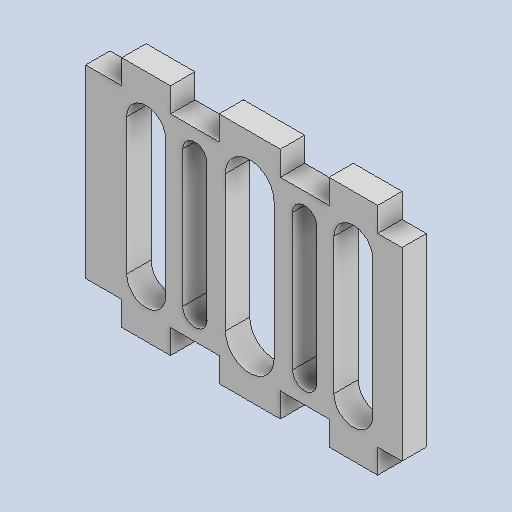
# Autodesk Inventor part: CalfFrontL
Saved by Autodesk Inventor 2025.2 (Build 292293000, 293)
## iProperties
Created: 2025-06-24
Part Number: CalfFrontL
Material: Generic
Document SubType Name: Modeling
Designer: ricoa
Density: 1 g/cm^3
Appearance: Default
Author: ricoa
Autodesk Inventor part; units mm, degrees
ref_plane "YZ Plane" through (0, 0, 0) normal (1, 0, 0) x (0, 1, 0)
ref_plane "XZ Plane" through (0, 0, 0) normal (0, 1, 0) x (-1, 0, 0)
ref_plane "XY Plane" through (0, 0, 0) normal (0, 0, 1) x (1, 0, 0)
sketch "Sketch1" plane through (0, 0, 0) normal (0, 0, 1) x (1, 0, 0)
  line L0 (17.4303, 49.3434) -> (30, 49.3434) projected
  line L1 (-2.5697, 49.3434) -> (7.4303, 49.3434) projected
  line L2 (40, 49.3434) -> (50, 49.3434) projected
  line L3 (50, 49.3434) -> (50, 44.3434)
  line L4 (40, 49.3434) -> (40, 44.3434)
  line L5 (40, 44.3434) -> (30, 44.3434)
  line L6 (30, 44.3434) -> (30, 49.3434)
  line L7 (30, 49.3434) -> (17.4303, 49.3434)
  line L8 (17.4303, 49.3434) -> (17.4303, 44.3434)
  line L9 (17.4303, 44.3434) -> (7.4303, 44.3434)
  line L10 (7.4303, 44.3434) -> (7.4303, 49.3434)
  line L11 (-2.5697, 49.3434) -> (-2.5697, 44.3434)
  line L12 (-10, 44.3434) -> (-2.5697, 44.3434) projected
  line L13 (50, 44.3434) -> (55, 44.3434) projected
  line L14 (50, 44.3434) -> (50, 49.3434) projected
  line L15 (55, 44.3434) -> (55, 6.3434)
  line L16 (55, 25.3434) -> (-10, 25.3434) construction
  line L17 (-10, 44.3434) -> (-10, 6.3434)
  line L18 (-10, 6.3434) -> (-2.5697, 6.3434)
  line L19 (-2.5697, 6.3434) -> (-2.5697, 1.3434)
  line L20 (-2.5697, 1.3434) -> (7.4303, 1.3434)
  line L21 (7.4303, 1.3434) -> (7.4303, 6.3434)
  line L22 (7.4303, 6.3434) -> (17.4303, 6.3434)
  line L23 (17.4303, 6.3434) -> (17.4303, 1.3434)
  line L24 (17.4303, 1.3434) -> (30, 1.3434)
  line L25 (30, 1.3434) -> (30, 6.3434)
  line L26 (30, 6.3434) -> (40, 6.3434)
  line L27 (40, 6.3434) -> (40, 1.3434)
  line L28 (40, 1.3434) -> (50, 1.3434)
  line L29 (50, 1.3434) -> (50, 6.3434)
  line L30 (50, 6.3434) -> (55, 6.3434)
  dimension "d2" = 5
  dimension "d3" = 5
  dimension "d4" = 38
  dimension "d5" = 5
  constraints: 50 end point, 11 perpendicular, 10 point on line, 5 vertical, 2 horizontal, 1 midpoint, 1 parallel
  measures "d2" distance of L2.end L3.end
  measures "d3" distance of L1.start L11.end
  measures "d4" distance of L13.end L15.end
  measures "d5" distance of L18.end L19.end
extrude "Extrusion1" add sketch "Sketch1" along normal blind 5
sketch "Sketch2" plane through (0, 0, 5) normal (0, 0, 1) x (1, 0, 0)
  line L0 (17.4303, 44.3434) -> (7.4303, 44.3434) projected
  line L1 (7.4303, 44.3434) -> (7.4303, 49.3434) projected
  line L2 (7.4303, 49.3434) -> (-2.5697, 49.3434) projected
  line L3 (-2.5697, 49.3434) -> (-2.5697, 44.3434) projected
  line L4 (-2.5697, 44.3434) -> (-10, 44.3434) projected
  line L5 (-10, 44.3434) -> (-10, 6.3434) projected
  line L6 (-10, 6.3434) -> (-2.5697, 6.3434) projected
  line L7 (-2.5697, 6.3434) -> (-2.5697, 1.3434) projected
  line L8 (-2.5697, 1.3434) -> (7.4303, 1.3434) projected
  line L9 (7.4303, 1.3434) -> (7.4303, 6.3434) projected
  line L10 (7.4303, 6.3434) -> (17.4303, 6.3434) projected
  line L11 (17.4303, 6.3434) -> (17.4303, 1.3434) projected
  line L12 (17.4303, 1.3434) -> (30, 1.3434) projected
  line L13 (30, 1.3434) -> (30, 6.3434) projected
  line L14 (30, 6.3434) -> (40, 6.3434) projected
  line L15 (40, 6.3434) -> (40, 1.3434) projected
  line L16 (40, 1.3434) -> (50, 1.3434) projected
  line L17 (50, 1.3434) -> (50, 6.3434) projected
  line L18 (50, 6.3434) -> (55, 6.3434) projected
  line L19 (55, 6.3434) -> (55, 44.3434) projected
  line L20 (55, 44.3434) -> (50, 44.3434) projected
  line L21 (50, 44.3434) -> (50, 49.3434) projected
  line L22 (50, 49.3434) -> (40, 49.3434) projected
  line L23 (40, 49.3434) -> (40, 44.3434) projected
  line L24 (40, 44.3434) -> (30, 44.3434) projected
  line L25 (30, 44.3434) -> (30, 49.3434) projected
  line L26 (30, 49.3434) -> (17.4303, 49.3434) projected
  line L27 (17.4303, 49.3434) -> (17.4303, 44.3434) projected
  line L28 (2.4303, 1.3434) -> (2.4303, 11.3434)
  line L29 (2.4303, 49.3434) -> (2.4303, 39.3434)
  line L30 (2.4303, 11.3434) -> (2.4303, 39.3434) construction
  line L31 (6.4303, 11.3434) -> (6.4303, 39.3434)
  line L32 (-1.5697, 39.3434) -> (-1.5697, 11.3434)
  arc A0 (-1.5697, 11.3434) -> (6.4303, 11.3434) centre (2.4303, 11.3434) ccw
  arc A1 (6.4303, 39.3434) -> (-1.5697, 39.3434) centre (2.4303, 39.3434) ccw
  line L33 (23.7152, 11.3434) -> (23.7152, 39.3434) construction
  line L34 (28.7152, 11.3434) -> (28.7152, 39.3434)
  line L35 (18.7152, 39.3434) -> (18.7152, 11.3434)
  arc A2 (18.7152, 11.3434) -> (28.7152, 11.3434) centre (23.7152, 11.3434) ccw
  arc A3 (28.7152, 39.3434) -> (18.7152, 39.3434) centre (23.7152, 39.3434) ccw
  line L36 (45, 11.3434) -> (45, 39.3434) construction
  line L37 (49, 11.3434) -> (49, 39.3434)
  line L38 (41, 39.3434) -> (41, 11.3434)
  arc A4 (41, 11.3434) -> (49, 11.3434) centre (45, 11.3434) ccw
  arc A5 (49, 39.3434) -> (41, 39.3434) centre (45, 39.3434) ccw
  line L39 (35, 11.3434) -> (35, 39.3434) construction
  line L40 (37.5, 11.3434) -> (37.5, 39.3434)
  line L41 (32.5, 39.3434) -> (32.5, 11.3434)
  arc A6 (32.5, 11.3434) -> (37.5, 11.3434) centre (35, 11.3434) ccw
  arc A7 (37.5, 39.3434) -> (32.5, 39.3434) centre (35, 39.3434) ccw
  line L42 (12.4303, 11.3434) -> (12.4303, 39.3434) construction
  line L43 (14.9303, 11.3434) -> (14.9303, 39.3434)
  line L44 (9.9303, 39.3434) -> (9.9303, 11.3434)
  arc A8 (9.9303, 11.3434) -> (14.9303, 11.3434) centre (12.4303, 11.3434) ccw
  arc A9 (14.9303, 39.3434) -> (9.9303, 39.3434) centre (12.4303, 39.3434) ccw
  point P0 (0, 0)
  point P1 (2.4303, 25.3434)
  point P2 (23.7152, 25.3434)
  point P3 (45, 25.3434)
  point P4 (35, 25.3434)
  point P5 (12.4303, 25.3434)
  dimension "d6" = 10
  dimension "d7" = 10
  dimension "d8" = 8
  dimension "d9" = 10
  dimension "d10" = 8
  dimension "d11" = 5
  dimension "d12" = 5
  constraints: 44 end point, 20 point on circle, 20 tangent, 10 centre point, 7 midpoint, 7 parallel, 5 vertical
  measures "d6" distance of L28.start L28.end
  measures "d7" distance of L29.start L29.end
  measures "d8" diameter of A1
  measures "d9" diameter of A3
  measures "d10" diameter of A5
  measures "d11" diameter of A7
  measures "d12" diameter of A9
extrude "Extrusion2" cut sketch "Sketch2" against normal blind 5 contours A1 L31 A0 L32 | A2 L35 A3 L34 | A4 L38 A5 L37 | A6 L41 A7 L40 | A8 L44 A9 L43
body "Solid1"
